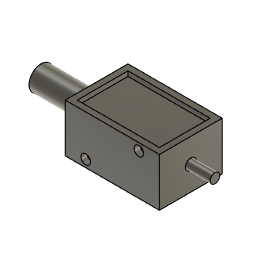
Player Piano Mechanism (Autodesk Fusion 360 archive; units mm, degrees)
design "JF-1038B Solenoid"
Autodesk Fusion 360 part; units mm, degrees
note: some values were not read from the file. Set by a fixed rule: which face or edge a step refers to.
sketch "Sketch1" plane through (0, 0, 0) normal (0, 1, 0) x (1, 0, 0)
  line L0 (84.6778, 11.5) -> (45.6778, 11.5)
  line L1 (45.6778, 11.5) -> (45.6778, -8.5)
  line L2 (45.6778, -8.5) -> (84.6778, -8.5)
  line L3 (84.6778, -8.5) -> (84.6778, 11.5)
  line L4 (84.6778, -8.5) -> (76.1778, -8.5)
  line L5 (76.1778, -8.5) -> (76.1778, -5.5) construction
  circle A0 centre (76.1778, -5.5) radius 2
  line L6 (76.1778, -5.5) -> (54.1778, -5.5) construction
  line L7 (54.1778, -5.5) -> (54.1778, 8.5) construction
  line L8 (54.1778, 8.5) -> (76.1778, 8.5) construction
  line L9 (76.1778, 8.5) -> (76.1778, -5.5) construction
  circle A1 centre (54.1778, 8.5) radius 2
  line L10 (81.1778, -22.5) -> (49.1778, -22.5)
  line L11 (49.1778, -22.5) -> (49.1778, -3.5)
  dimension "d1" = 8.5
  dimension "d2" = 3
  dimension "d3" = 4
  dimension "d4" = 22
  dimension "d5" = 14
  dimension "d6" = 4
  dimension "d17" = 39
  dimension "d43" = 20
  constraint horizontal L0
  constraint vertical L1
  constraint horizontal L2
  constraint vertical L3
  constraint perpendicular L3 L4
  constraint perpendicular L2 L5
  constraint coincident L5.end A0.centre
  constraint horizontal L6
  constraint vertical L7
  constraint horizontal L8
  constraint vertical L9
  constraint coincident L7.end L8.start
  measures "d1" distance of L2.end L4.end
  measures "d2" distance of L4.end L5.end
  measures "d3" diameter of A0
  measures "d4" distance of L5.end L6.end
  measures "d5" distance of L5.end L8.end
  measures "d6" diameter of A1
  measures "d17" distance of L0.start L0.end
  measures "d43" distance of L0.start L2.end
extrude "Extrude1" add sketch "Sketch1" along normal blind 26 contours L0 L1 L2 L3 L4 | A0 | A1 makes body 1
shell "Shell1" thickness 2.5 removed faces 1 at (71.6778, 17.3333, -11.5) on bodies 1
extrude "Extrude2" cut 3 faces at (48.5111, 9.5, 6) (58.1778, 16.5, 6) (80.1778, 16.5, 6) along direction (0, 0, -1) up to surface end surface through (45.6778, 0, 8.5) normal (0, 0, 1) offset 0 on bodies 1 bodies 1
extrude "Extrude3" cut sketch "Sketch1" along normal up to surface (2.5 mm away) contours A0 | A1 bodies 1
sketch "Sketch2" plane through (45.6778, 0, 0) normal (-1, 0, 0) x (0, -1, 0)
  line L0 (0, -11.5) -> (0, 8.5)
  line L1 (0, 8.5) -> (-26, 8.5)
  line L2 (-26, 8.5) -> (-26, -11.5)
  line L3 (-26, -11.5) -> (0, -11.5)
  line L4 (0, 8.5) -> (-26, -11.5) construction
  circle A0 centre (-13, -1.5) radius 5
  dimension "d9" = 10
  constraint coincident L0.end L1.start
  constraint coincident L2.end L3.start
  constraint midpoint L4 A0.centre
  measures "d9" diameter of A0
extrude "Extrude4" add sketch "Sketch2" along normal blind 23 separate body contours A0 makes body 2
extrude "Extrude5" add 1 faces at (45.6778, 14.5926, -1.0087) along direction (1, 0, 0) up to surface (36.5 mm away) on bodies 2 bodies 2
sketch "Sketch3" plane through (0, 0, -11.5) normal (0, 0, -1) x (1, 0, 0)
  line L0 (48.1778, -23.5) -> (48.1778, -2.5)
  line L1 (48.1778, -2.5) -> (82.1778, -2.5)
  line L2 (82.1778, -2.5) -> (82.1778, -23.5)
  line L3 (82.1778, -23.5) -> (48.1778, -23.5)
  line L4 (84.6778, 0) -> (45.6778, 0)
  line L5 (45.6778, 0) -> (45.6778, -26)
  line L6 (45.6778, -26) -> (84.6778, -26)
  line L7 (84.6778, -26) -> (84.6778, 0)
  line L8 (81.1778, -22.5) -> (49.1778, -22.5)
  line L9 (49.1778, -22.5) -> (49.1778, -3.5)
  line L10 (49.1778, -3.5) -> (81.1778, -3.5)
  line L11 (81.1778, -3.5) -> (81.1778, -22.5)
  dimension "d21" = 1
extrude "Extrude6" add sketch "Sketch3" against normal up to surface (18 mm away) from surface at -1 separate body contours L8 L9 L10 L11 makes body 3
sketch "Sketch4" plane through (82.1778, 0, 0) normal (1, 0, 0) x (0, 1, 0)
  circle A0 centre (13, -1.5) radius 5
  circle A1 centre (13, -1.5) radius 2
  dimension "d25" = 4
  constraint concentric A0 A1
  measures "d25" diameter of A1
extrude "Extrude7" add sketch "Sketch4" along normal up to surface (2.5 mm away) contours A1 bodies 2
combine "Combine3" operation cut target body 3 tool bodies 2 keep tools
extrude "Extrude8" cut 1 faces at (82.1778, 9.0186, -1.7484) along direction (-1, 0, 0) blind 10 on bodies 2 bodies 2
combine "Combine4" operation cut target body 1 tool bodies 2 keep tools
move_face "OffsetFaces3" offset -0.25 1 faces at (83.8445, 14.9975, -1.5997) on bodies 1
copy_body "Body->Comp1" bodies 3 removing the originals makes body 4 in component "Coil"
copy_body "Body->Comp2" bodies 1 removing the originals makes body 5 in component "Frame"
copy_body "Body->Comp3" bodies 2 removing the originals makes body 6 in component "Plunger"
sketch "Sketch5" plane through (0, 0, 0) normal (0, -1, 0) x (1, 0, 0)
  circle A0 centre (76.1778, 5.5) radius 2
  circle A1 centre (54.1778, -8.5) radius 2
  line L0 (45.6778, -11.5) -> (84.6778, -11.5)
  line L1 (84.6778, -11.5) -> (84.6778, 8.5)
  line L2 (84.6778, 8.5) -> (45.6778, 8.5)
  line L3 (45.6778, 8.5) -> (45.6778, -11.5)
extrude "Extrude2'" add 1 faces at (84.6778, 12.363, -1.4978) along direction (1, 0, 0) blind 10 on bodies 6 bodies 6 in component "Plunger"
component "Coil" placed x (1, 0, 0) y (0, 1, 0) z (0, 0, 1) at (0, 0, 0)
component "Frame" placed x (1, 0, 0) y (0, 1, 0) z (0, 0, 1) at (0, 0, 0)
component "Plunger" placed x (1, 0, 0) y (0, 1, 0) z (0, 0, 1) at (0, 0, 0)
equation "d1 = ( Body_Length - 22 mm ) / 2"
equation "d3 = Mouting_Hole_Diameter"
equation "d6 = Mouting_Hole_Diameter"
equation "d7 = Body_Width"
equation "d15 = Thick_Rod_Length"
equation "d17 = Body_Length"
equation "Mouting_Hole_Diameter = 4 mm"
equation "Thick_Rod_Length = 23 mm"
equation "Overall_Length = 72 mm"
equation "Body_Length = 39 mm" comment "From the perspective of looking down on the solenoid with the mouting holes facing the side"
equation "Body_Width = 26 mm" comment "From the perspective of looking down on the solenoid with the mouting holes facing the side"
equation "Body_Height = 20 mm" comment "From the perspective of looking down on the solenoid with the mouting holes facing the side"
equation "d43 = Body_Height"
